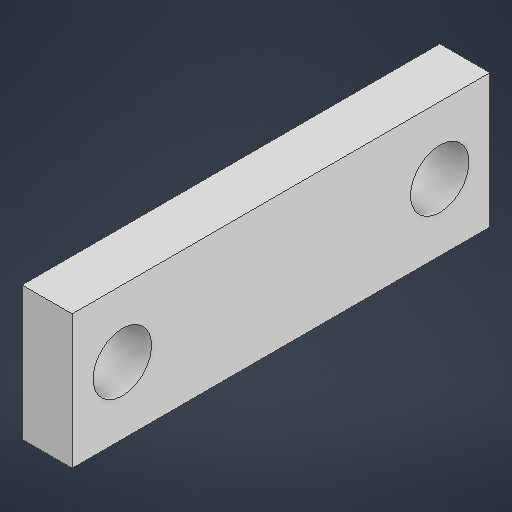
# Autodesk Inventor part: Sensor
Saved by Autodesk Inventor 2025.2 (Build 292293000, 293)
## iProperties
Created: 2025-06-04
Part Number: Sensor
Material: Genérico
Document SubType Name: Modeling
Designer: Niko
Density: 1 g/cm^3
Appearance: Valor por defecto
Author: Niko
Autodesk Inventor part; units mm, degrees
ref_plane "YZ Plane" through (0, 0, 0) normal (1, 0, 0) x (0, 1, 0)
ref_plane "XZ Plane" through (0, 0, 0) normal (0, 1, 0) x (-1, 0, 0)
ref_plane "XY Plane" through (0, 0, 0) normal (0, 0, 1) x (1, 0, 0)
sketch "Boceto1" plane through (0, 0, 0) normal (1, 0, 0) x (0, 1, 0)
  circle A0 centre (0, -10) radius 1.75
  line L0 (-4, 12) -> (-4, -13)
  line L1 (-4, -13) -> (4, -13)
  line L2 (4, 12) -> (4, -13)
  circle A1 centre (0, 9) radius 1.75
  line L3 (-4, 12) -> (4, 12)
  point P0 (0, 0)
  constraints: 8 end point, 2 centre point, 1 vertical
extrude "Extrusión3" add sketch "Boceto1" along normal blind 3
